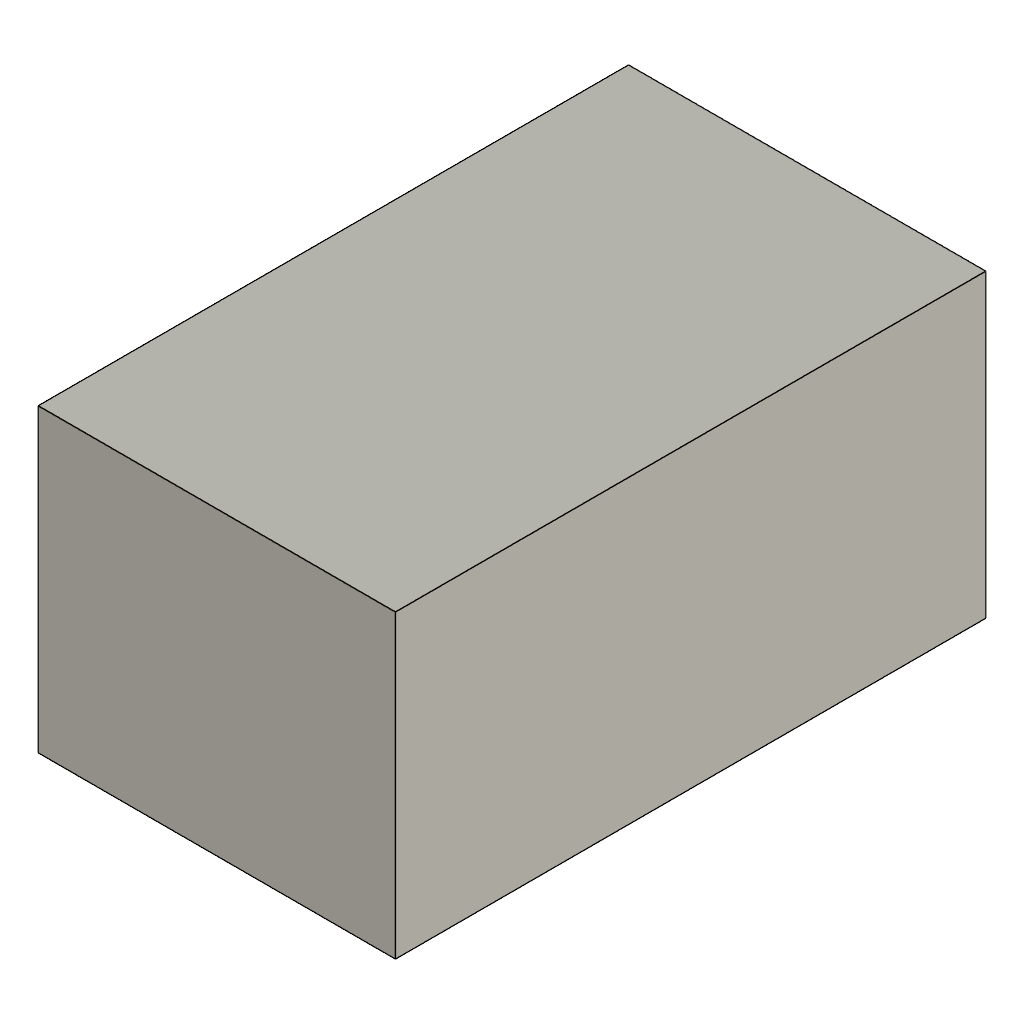
BaselineRestored (Autodesk Fusion 360 design; units mm, degrees)
Autodesk Fusion 360 part; units mm, degrees
sketch "Encoder Rectangle" plane through (0, 0, 0) normal (0, 0, 1) x (1, 0, 0)
  line L0 (0, 0) -> (16.4, 0)
  line L1 (16.4, 0) -> (16.4, 27.1)
  line L2 (16.4, 27.1) -> (0, 27.1)
  line L3 (0, 27.1) -> (0, 0)
  dimension "d6" = 16.4
  dimension "d7" = 27.1
  constraint horizontal L0
  constraint vertical L1
  constraint horizontal L2
  constraint vertical L3
  measures "d6" horizontal distance of L0.start L0.end
  measures "d7" vertical distance of L0.start L2.end
extrude "Encoder Extrusion" add sketch "Encoder Rectangle" along normal blind 13.8
equation "kitHeight = 13.8 mm"
equation "d2 = kitHeight"
equation "kitWidth = 16.4 mm"
equation "kitDepth = 27.1 mm"
equation "d6 = kitWidth"
equation "d7 = kitDepth"
